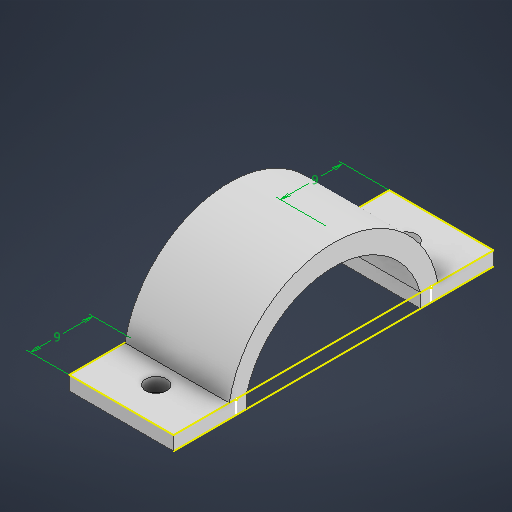
# Autodesk Inventor part: trzymanie_silnika
Saved by Autodesk Inventor 2026.1 (Build 301233020, 233B)
## iProperties
Created: 2026-07-11
Part Number: trzymanie_silnika
Material: Ogólny
Document SubType Name: Modeling
Designer: Nitro
Density: 1 g/cm^3
Appearance: Domyślna
Author: Nitro
Autodesk Inventor part; units mm, degrees
ref_plane "YZ Plane" through (0, 0, 0) normal (1, 0, 0) x (0, 1, 0)
ref_plane "XZ Plane" through (0, 0, 0) normal (0, 1, 0) x (-1, 0, 0)
ref_plane "XY Plane" through (0, 0, 0) normal (0, 0, 1) x (1, 0, 0)
sketch "Szkic1" plane through (0, 0, 0) normal (0, 1, 0) x (-1, 0, 0)
  line L0 (0, 0) -> (15, 0)
  line L1 (15, 0) -> (15, -46)
  line L2 (15, -46) -> (0, -46)
  line L3 (0, -46) -> (0, 0)
  point P0 (7.5, -5)
  point P1 (7.5, -41)
  point P2 (7.5, 0)
  dimension "d0" = 15
  dimension "d1" = 46
  dimension "d2" = 36
  dimension "d3" = 5
  constraints: 8 end point, 2 parallel, 1 horizontal, 1 midpoint, 1 perpendicular
  measures "d0" distance of L1.end L2.end
  measures "d1" distance of L0.end L1.end
  measures "d2" distance of point (7.5, -41) point (7.5, -5)
  measures "d3" distance of point (7.5, 0) point (7.5, -5)
extrude "Wyciągnięcie proste1" add sketch "Szkic1" along normal blind 2
sketch "Szkic2" plane through (0, 2, 0) normal (0, 1, 0) x (1, 0, 0)
  line L0 (0, 46) -> (-15, 46) projected
  line L1 (-15, 46) -> (-15, 0) projected
  line L2 (-15, 0) -> (0, 0) projected
  line L3 (0, 0) -> (0, 46) projected
  point P0 (-7.5, 5)
  point P1 (-7.5, 41)
  dimension "d6" = 36
  dimension "d7" = 5
  dimension "d8" = 7.5
  dimension "d9" = 7.5
  measures "d6" distance of point (-7.5, 41) point (-7.5, 5)
  measures "d7" distance from line of L2 point (-7.5, 5)
  measures "d8" distance from line of L3 point (-7.5, 41)
  measures "d9" distance from line of L3 point (-7.5, 5)
hole "Otwór1" at (-7.5, 2, -5) at (-7.5, 2, -41) direction (0, -1, 0) diameter 3 depth 10
sketch "Szkic19" plane through (0, 2, 0) normal (0, 1, 0) x (1, 0, 0)
  line L0 (-15, 46) -> (-15, 0) projected
  line L1 (-15, 9) -> (0, 9)
  line L2 (0, 0) -> (0, 46) projected
  line L3 (-15, 37) -> (0, 37)
  line L4 (-15, 0) -> (0, 0) projected
  line L5 (0, 46) -> (-15, 46) projected
  dimension "d118" = 9
  dimension "d119" = 9
  constraints: 4 end point, 2 horizontal, 2 point on line
  measures "d118" distance between parallel lines of L4 L1
  measures "d119" distance between parallel lines of L5 L3
sketch "Szkic20" plane through (0, 0, 0) normal (1, 0, 0) x (0, 0, -1)
  line L0 (9, 2) -> (9, 0)
  line L1 (0, 0) -> (46, 0) projected
  line L2 (37, 2) -> (37, 0)
  point P0 (9, 2)
  point P1 (37, 2)
  constraints: 4 end point, 2 vertical, 1 point on line
sketch "Szkic24" plane through (0, 0, 0) normal (1, 0, 0) x (0, 0, -1)
  line L0 (0, 0) -> (46, 0) projected
  line L1 (46, 0) -> (46, 2) projected
  line L2 (0, 2) -> (46, 2) projected
  line L3 (0, 0) -> (0, 2) projected
  line L4 (46, 2) -> (0, 2) projected
  arc A0 (35.5, 2) -> (10.5, 2) centre (23, -1.5707) ccw
  arc A1 (38, 2) -> (8, 2) centre (23, -0.8089) ccw
  point P0 (38, 2)
  point P1 (8, 2)
  dimension "d131" = 10.5
  dimension "d132" = 10.5
  dimension "d133" = 13
  dimension "d134" = 8
  dimension "d135" = 8
  constraints: 4 point on circle, 4 point on line, 2 centre point
  measures "d131" distance from line of L1 A0.start
  measures "d132" distance from line of L3 A0.end
  measures "d133" radius of A0
  measures "d134" distance from line of L1 A1.start
  measures "d135" distance from line of L3 A1.end
extrude "Wyciągnięcie proste11" add sketch "Szkic24" against normal blind 15 contours A1 L2 A0
sketch "Szkic25" plane through (0, 0, 0) normal (1, 0, 0) x (0, 0, -1)
  line L0 (10.5, 2) -> (35.5, 2) projected
  arc A0 (35.5, 2) -> (10.5, 2) centre (23, -1.5707) ccw projected
  arc A1 (38, 2) -> (8, 2) centre (23, -0.8089) ccw projected
  line L1 (0, 2) -> (8, 2) projected
  line L2 (0, 0) -> (0, 2) projected
  line L3 (0, 0) -> (46, 0) projected
  line L4 (46, 0) -> (46, 2) projected
  line L5 (38, 2) -> (46, 2) projected
  line L6 (10.5, 2) -> (10.5, 0)
  line L7 (35.5, 2) -> (35.5, 0)
  constraints: 4 end point, 2 perpendicular, 2 point on line
extrude "Wyciągnięcie proste12" cut sketch "Szkic25" against normal blind 15 contours L0 L7 L3 L6
equation "\"d36\" = 55deg"
equation "\"Szkic6_Pitch\" = 0.5"
equation "\"d54\" = 55deg"
equation "\"Szkic8_Pitch\" = 0.5"
equation "\"d88\" = 55deg"
equation "\"Szkic15_Pitch\" = 0.5"
equation "\"d106\" = 55deg"
equation "\"Szkic17_Pitch\" = 0.5"
